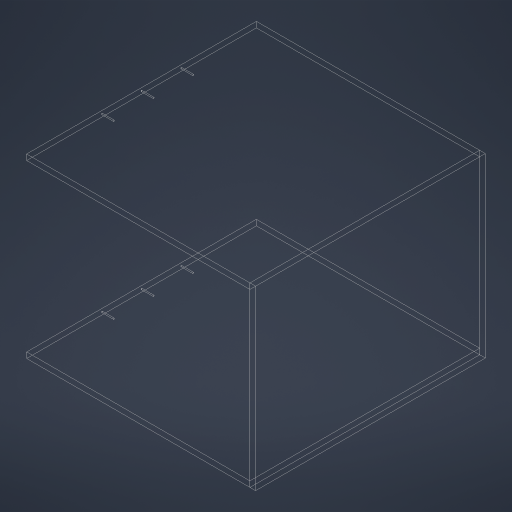
# Autodesk Inventor part: Деталь1
Saved by Autodesk Inventor 2023.4 (Build 274418000, 418)
## iProperties
Created: 2026-09-26
Part Number: Деталь1
Material: Типовые
Document SubType Name: Modeling
Designer: desig
Density: 1 g/cm^3
Appearance: По умолчанию
Author: desig
Autodesk Inventor part; units mm, degrees
ref_plane "YZ Plane" through (0, 0, 0) normal (1, 0, 0) x (0, 1, 0)
ref_plane "XZ Plane" through (0, 0, 0) normal (0, 1, 0) x (-1, 0, 0)
sketch "Эскиз1" plane through (0, 0, 0) normal (0, 1, 0) x (-1, 0, 0)
  line L0 (0, 0) -> (-16, 0)
  line L1 (-16, 0) -> (-16, -648.6531)
  line L2 (-16, -648.6531) -> (0, -648.6531)
  line L3 (0, -648.6531) -> (0, 0)
  line L4 (-646.4743, 0) -> (-662.4743, 0)
  line L5 (-662.4743, 0) -> (-662.4743, -648.6531)
  line L6 (-662.4743, -648.6531) -> (-646.4743, -648.6531)
  line L7 (-646.4743, -648.6531) -> (-646.4743, 0)
  line L8 (-16, -648.6531) -> (-646.4743, -648.6531)
  line L9 (-16, 0) -> (-646.4743, 0)
  dimension "d0" = 16
  dimension "d1" = 16
  dimension "d46" = 648.653
  dimension "d47" = 662.474
  constraints: 20 end point, 4 parallel, 3 horizontal, 3 perpendicular, 2 point on line
  measures "d0" distance of L1.end L2.end
  measures "d1" distance of L5.end L6.end
  measures "d46" distance of L2.end L0.start
  measures "d47" distance between parallel lines of L5 L3
extrude "Выдавливание1" add sketch "Эскиз1" along normal blind 500 contours L3 L2 L1 L0
extrude "Выдавливание2" add sketch "Эскиз1" against normal blind 16 from surface at 500 separate body contours L1 L8 L7 L9
extrude "Выдавливание3" add sketch "Эскиз1" along normal blind 16 separate body contours L1 L8 L7 L9
extrude "Выдавливание4" add sketch "Эскиз1" along normal up to surface (500 mm away) separate body contours L7 L6 L5 L4
ref_plane "DrillingSketch_OffsetPlane_1" through (0, 484, 0) normal (-1, 0, 0) x (0, 0, 1)
sketch "DrillingSketch_1" plane through (0, 484, 0) normal (-1, 0, 0) x (0, 0, 1)
  line L0 (0, 0) -> (-648.6531, 0) projected
  line L1 (0, 16) -> (0, 0) projected
  line L2 (0, 16) -> (-648.6531, 16) projected
  line L3 (-648.6531, 0) -> (-648.6531, 16) projected
  line L4 (0, 8) -> (-648.6531, 8) construction
  line L5 (-324.3266, 8) -> (-324.3266, -12) construction
  line L6 (-324.3266, 8) -> (-324.3266, 0) construction
  line L7 (-648.6531, -484) -> (0, -484) projected
  line L8 (0, -484) -> (0, -468) projected
  line L9 (-648.6531, -468) -> (0, -468) projected
  line L10 (-648.6531, -484) -> (-648.6531, -468) projected
  line L11 (0, -476) -> (-648.6531, -476) construction
  line L12 (-324.3266, -476) -> (-324.3266, -486) construction
  line L13 (-324.3266, -476) -> (-324.3266, -484) construction
  point P0 (-212.3266, 8)
  point P1 (-436.3266, 8)
  point P2 (-244.3266, 8)
  point P3 (-404.3266, 8)
  point P4 (-212.3266, -476)
  point P5 (-436.3266, -476)
  point P6 (-244.3266, -476)
  point P7 (-404.3266, -476)
  dimension "Толщина_каркаса_ящика" = 16
  dimension "Желаемый_отступ_присадки_каркаса1_стяжка" = 200
  dimension "Long_edge_1" = 648.6531
  dimension "Расстояние_между_точками" = 224
  dimension "d3782" = 32
  dimension "Long_edge_2" = 648.6531
  dimension "Расстояние_между_точками_2" = 224
  dimension "d3785" = 32
  constraints: 12 end point, 10 point on line, 8 midpoint, 4 perpendicular, 4 symmetric about line
  measures "Long_edge_1" distance of L4.start L4.end
  measures "Расстояние_между_точками" distance of point (-436.327, 8) point (-212.327, 8)
  measures "d3782" distance of point (-212.327, 8) point (-244.327, 8)
  measures "Long_edge_2" distance of L11.start L11.end
  measures "Расстояние_между_точками_2" distance of point (-436.327, -476) point (-212.327, -476)
  measures "d3785" distance of point (-212.327, -476) point (-244.327, -476)
hole "Confirmat 2pcs counterbore" at (0, 492, -212.3266) at (0, 492, -436.3266) at (0, 8, -212.3266) at (0, 8, -436.3266) direction (1, 0, 0) diameter 3 depth 50 counterbore diameter 4.9 counterbore depth 16
hole "Confirmat counterbore" at (0, 492, -324.3266) at (0, 8, -324.3266) direction (1, 0, 0) diameter 3 depth 50 counterbore diameter 4.9 counterbore depth 16
equation "\"d0\" = Толщина_каркаса"
equation "\"d1\" = Толщина_каркаса"
equation "\"d5\" = Толщина_каркаса"
equation "\"d7\" = Толщина_каркаса"
equation "\"Толщина_каркаса_ящика\" = 16"
equation "\"Желаемый_отступ_присадки_каркаса1_стяжка\" = 200"
equation "\"Кол_конф\" = 3"
equation "\"Толщина_каркаса\" = 16"
equation "\"Стяжка_D\" = 15"
equation "\"Стяжка_h\" = 12.5"
equation "\"Стяжка_D_резьбыШтока\" = 5"
equation "\"Стяжка_D_телаШтока\" = 8"
equation "\"Стяжка_отступ\" = 34"
equation "\"Конфирмат_D_вПласть\" = 8"
equation "\"Конфирмат_D_вТорец\" = 5"
equation "\"Шкант_D\" = 8"
equation "\"Полкодержатель_D\" = 5"
equation "\"Полкодержатель_смещение_от_низа_полки\" = 5"
equation "\"Петля_D_присадки\" = 35"
equation "\"M_Конфирмат_глубина_резьбы\" = 35"
equation "\"M_Конфирмат_D_вПласть\" = 4.9"
equation "\"M_Конфирмат_D_вТорец\" = 3"
equation "\"Толщина_задн_ст_Володя\" = 3"
equation "\"Толщина_дна_ящика_Володя\" = 6"
equation "\"Минимальное_расстояния_от_заднСт_ящика_до_заднСт\" = 25"
equation "\"Западание_кромки_полки_за_каркас\" = 5"
equation "\"Keep_Excel_Params\" = 0"
equation "\"Стяжкаh_резьбаШтока_Петля\" = 13"
equation "\"Толщина_каркаса_МДФ\" = 16"
equation "\"Толщина_каркаса_ШПОН\" = 17"
equation "\"Отверстие_регулировка_опоры_D\" = 7.9"
equation "\"Наколка_D\" = 3"
equation "\"Keep_Excel_Params_Unitless\" = 0"
